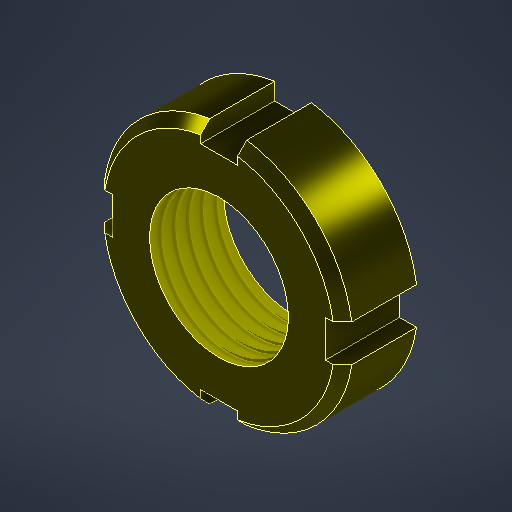
# Autodesk Inventor part: 8. Lock Nut M15
Saved by Autodesk Inventor 2025.2 (Build 292293000, 293)
## iProperties
Created: 2025-05-09
Part Number: 8. Lock Nut M15
Material: Steel, Mild
Document SubType Name: Modeling
Designer: trysm
Density: 7.85 g/cm^3
Appearance: Semi-Polished
Author: trysm
Autodesk Inventor part; units mm, degrees
ref_plane "YZ Plane" through (0, 0, 0) normal (1, 0, 0) x (0, 1, 0)
ref_plane "XZ Plane" through (0, 0, 0) normal (0, 1, 0) x (-1, 0, 0)
ref_plane "XY Plane" through (0, 0, 0) normal (0, 0, 1) x (1, 0, 0)
sketch "Sketch1" plane through (0, 0, 0) normal (0, 1, 0) x (-1, 0, 0)
  circle A0 centre (0, 0) radius 7.5
  line L0 (2, 11.5) -> (-2, 11.5)
  line L1 (-2, 11.5) -> (-2, 13.351)
  line L2 (2, 13.351) -> (2, 11.5)
  line L3 (2, 11.5) -> (-2, 15.5) construction
  line L4 (-2, 11.5) -> (2, 15.5) construction
  line L5 (-11.5, 2) -> (-11.5, -2)
  line L6 (-11.5, -2) -> (-13.351, -2)
  line L7 (-13.351, 2) -> (-11.5, 2)
  line L8 (-2, -11.5) -> (2, -11.5)
  line L9 (2, -11.5) -> (2, -13.351)
  line L10 (-2, -13.351) -> (-2, -11.5)
  line L11 (11.5, -2) -> (11.5, 2)
  line L12 (11.5, 2) -> (13.351, 2)
  line L13 (13.351, -2) -> (11.5, -2)
  arc A1 (13.351, 2) -> (2, 13.351) centre (0, 0) ccw
  arc A2 (2, -13.351) -> (13.351, -2) centre (0, 0) ccw
  arc A3 (-2, 13.351) -> (-13.351, 2) centre (0, 0) ccw
  arc A4 (-13.351, -2) -> (-2, -13.351) centre (0, 0) ccw
  point P0 (0, 12.5)
  point P1 (0, 10.5)
  point P2 (0, 13.5)
  point P3 (0, 13.5)
  point P4 (0, 11.5)
  point P5 (-12.5, 0)
  point P6 (-10.5, 0)
  point P7 (-11.5, 0)
  point P8 (-13.5, 0)
  point P9 (-13.5, 0)
  point P10 (0, -12.5)
  point P11 (0, -10.5)
  point P12 (0, -11.5)
  point P13 (0, -13.5)
  point P14 (0, -13.5)
  point P15 (12.5, 0)
  point P16 (10.5, 0)
  point P17 (11.5, 0)
  point P18 (13.5, 0)
  point P19 (13.5, 0)
  dimension "d1" = 15
  dimension "d24" = 2
  dimension "d25" = 4
  dimension "d26" = 11.5
  dimension "d27" = 13.351
  dimension "d30" = 360
  dimension "d32" = 13.5
  constraints: 28 end point, 8 point on circle, 5 centre point, 3 midpoint, 2 coincident, 2 vertical alignment, 1 horizontal, 1 parallel, 1 perpendicular, 49 other
  measures "d1" diameter of A0
  measures "d24" distance from line of L0 point (0, 13.5)
  measures "d25" distance between parallel lines of L2 L1
  measures "d26" distance of point (0, 0) point (0, 11.5)
  measures "d27" vertical distance of point (0, 0) L1.end
  measures "d32" radius of A1
extrude "Extrusion1" add sketch "Sketch1" along normal blind 8
chamfer "Chamfer2" distance 1 angle 45 4 edges at (-9.5459, 0, 9.5459) (9.5459, 0, 9.5459) (-9.5459, 0, -9.5459) (9.5459, 0, -9.5459)
thread "Thread2" size "M15x1.5" class "6H" standard "ANSI Metric M Profile" full length
body "Solid1"
